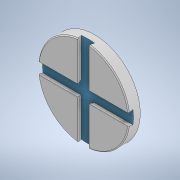
# Autodesk Inventor part: 24-10-25-base-Lawrence-A2213271-v1
Saved by Autodesk Inventor 2022 (Build 260153000, 153)
## iProperties
Created: 2024-10-25
Part Number: 24-10-25-base-Lawrence-A2213271-v1
Material: Generic
Document SubType Name: Modeling
Designer: Dell
Density: 1 g/cm^3
Appearance: Default
Author: Dell
Autodesk Inventor part; units mm, degrees
ref_plane "YZ Plane" through (0, 0, 0) normal (1, 0, 0) x (0, 1, 0)
ref_plane "XZ Plane" through (0, 0, 0) normal (0, 1, 0) x (-1, 0, 0)
ref_plane "XY Plane" through (0, 0, 0) normal (0, 0, 1) x (1, 0, 0)
sketch "Sketch1" plane through (0, 0, 0) normal (0, 0, 1) x (1, 0, 0)
  circle A0 centre (0, 0) radius 100
  dimension "d0" = 200
  constraints: 1 centre point, 1 coincident
  measures "d0" diameter of A0
extrude "Extrusion1" add sketch "Sketch1" along normal blind 25
sketch "Sketch2" plane through (0, 0, 25) normal (0, 0, 1) x (1, 0, 0)
  line L0 (105.1947, -12.5) -> (105.1947, 12.5)
  line L1 (-105.1947, 12.5) -> (-105.1947, -12.5)
  line L2 (-105.1947, -12.5) -> (105.1947, 12.5) construction
  line L3 (105.1947, -12.5) -> (-105.1947, 12.5) construction
  line L4 (12.5, -105) -> (-12.5, -105)
  line L5 (-12.5, 105) -> (12.5, 105)
  line L6 (12.5, -105) -> (-12.5, 105) construction
  line L7 (-12.5, -105) -> (12.5, 105) construction
  line L8 (-12.5, -105) -> (-12.5, -12.5)
  line L9 (-12.5, 12.5) -> (-12.5, 105)
  line L10 (105.1947, 12.5) -> (12.5, 12.5)
  line L11 (12.5, 105) -> (12.5, 12.5)
  line L12 (12.5, -12.5) -> (105.1947, -12.5)
  line L13 (12.5, -12.5) -> (12.5, -105)
  line L14 (-105.1947, -12.5) -> (-12.5, -12.5)
  line L15 (-12.5, 12.5) -> (-105.1947, 12.5)
  point P0 (0, 0)
  dimension "d4" = 25
  dimension "d5" = 25
  dimension "d6" = 210
  constraints: 32 end point, 10 parallel, 4 midpoint, 4 perpendicular, 3 horizontal
  measures "d4" distance of L0.end L0.start
  measures "d5" distance of L5.start L5.end
  measures "d6" distance of L4.end L5.start
extrude "Extrusion2" cut sketch "Sketch2" against normal blind 10 draft 12
chamfer "Chamfer1" distance 2 angle 45 4 edges at (-70.7107, 70.7107, 25) (70.7107, 70.7107, 25) (70.7107, -70.7107, 25) (-70.7107, -70.7107, 25)
sketch "Sketch3" plane through (0, 0, 0) normal (0, 0, -1) x (-1, 0, 0)
  circle A0 centre (0, 0) radius 80 construction
  circle A1 centre (0, 80) radius 12.5
  dimension "d12" = 160
  dimension "d13" = 25
  constraints: 1 centre point, 1 coincident, 1 vertical alignment, 2 other
  measures "d13" diameter of A1
extrude "Extrusion3" add sketch "Sketch3" along normal blind 4
fillet "Fillet1" radius 2 1 edges at (12.5, 80, 0)
pattern_circular "Circular Pattern1" count 4 over 360 about axis through (0, 0, 0) along (0, 0, 1) of "Extrusion3", "Fillet1"
body "Solid1"
